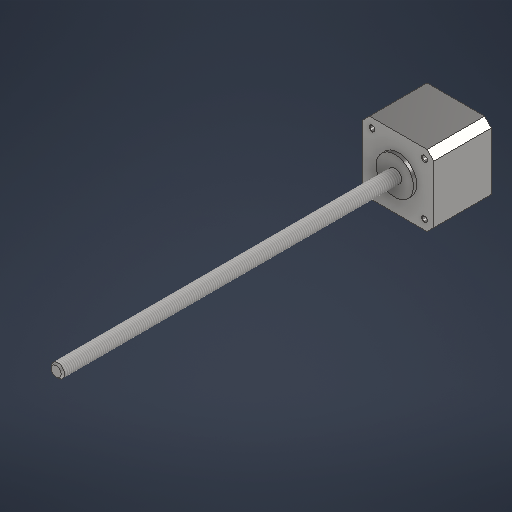
# Autodesk Inventor part: stepper_motor_42x34mm
Saved by Autodesk Inventor 2026.2 (Build 302298010, 298A)
## iProperties
Created: 2026-10-26
Part Number: stepper_motor_42x34mm
Material: Acier inoxydable
Document SubType Name: Modeling
Designer: User
Density: 8 g/cm^3
Appearance: Semi-poli
Author: User
Autodesk Inventor part; units mm, degrees
ref_plane "YZ Plane" through (0, 0, 0) normal (1, 0, 0) x (0, 1, 0)
ref_plane "XZ Plane" through (0, 0, 0) normal (0, 1, 0) x (-1, 0, 0)
ref_plane "XY Plane" through (0, 0, 0) normal (0, 0, 1) x (1, 0, 0)
sketch "Esquisse1" plane through (0, 0, 0) normal (0, 0, 1) x (1, 0, 0)
  line L0 (-21, 21) -> (21, 21)
  line L1 (21, 21) -> (21, -21)
  line L2 (21, -21) -> (-21, -21)
  line L3 (-21, -21) -> (-21, 21)
  point P0 (0, 0)
  dimension "d0" = 42
  dimension "d1" = 42
  dimension "d2" = 21
  dimension "d3" = 21
  constraints: 8 end point, 2 parallel, 1 horizontal, 1 perpendicular
  measures "d0" distance of L0.start L0.end
  measures "d1" distance of L2.end L0.start
  measures "d2" distance from line of L3 point (0, 0)
  measures "d3" distance from line of L2 point (0, 0)
extrude "Extrusion1" add sketch "Esquisse1" along normal blind 34
sketch "Esquisse2" plane through (0, 0, 34) normal (0, 0, 1) x (1, 0, 0)
  circle A0 centre (0, 0) radius 11
  dimension "d6" = 22
  constraints: 1 centre point, 1 coincident
  measures "d6" diameter of A0
extrude "Extrusion2" add sketch "Esquisse2" along normal blind 2
sketch "Esquisse3" plane through (0, 0, 36) normal (0, 0, 1) x (1, 0, 0)
  circle A0 centre (0, 0) radius 4
  circle A1 centre (0, 0) radius 11 projected
  dimension "d9" = 8
  constraints: 1 centre point, 1 concentric
  measures "d9" diameter of A0
extrude "Extrusion3" add sketch "Esquisse3" along normal blind 200 contours A0
chamfer "Chanfrein1" distance 4 angle 45 4 edges at (21, 21, 17) (21, -21, 17) (-21, -21, 17) (-21, 21, 17)
sketch "Esquisse5" plane through (0, 0, 34) normal (0, 0, 1) x (1, 0, 0)
  line L0 (17, 21) -> (-17, 21) projected
  line L1 (-21, 17) -> (-21, -17) projected
  circle A0 centre (-15.5, 15.5) radius 1.5
  point P0 (0, 0)
  dimension "d24" = 5.5
  dimension "d25" = 5.5
  dimension "d26" = 3
  constraints: 1 centre point
  measures "d24" distance from line of L0 A0.centre
  measures "d25" distance from line of L1 A0.centre
  measures "d26" diameter of A0
hole "Perçage2" at (-15.5, 15.5, 34) direction (0, 0, -1) diameter 3 depth 4.5 countersink diameter 3.5 countersink angle 90
pattern_circular "Réseau circulaire1" count 4 over 360 about axis through (0, 0, -10) along (0, 0, 1) of "Perçage2"
thread "Filetage1" size "M8x1.25" class "6g" standard "ANSI Metric M Profile" full length
chamfer "Chanfrein2" distance 1 angle 45 1 edges at (-4, 0, 236)
equation "\"d0\" = L_stepper_motor"
equation "\"d1\" = L_stepper_motor"
equation "\"d2\" = 0.5 * L_stepper_motor"
equation "\"d3\" = d2"
equation "\"d4\" = H_stepper_motor"
equation "\"d6\" = D_ledge"
equation "\"d7\" = H_ledge"
equation "\"d9\" = D_screw"
equation "\"d10\" = L_screw"
equation "\"L_stepper_motor\" = 42"
equation "\"H_stepper_motor\" = 34"
equation "\"L_screw\" = 200"
equation "\"D_screw\" = 8"
equation "\"H_ledge\" = 2"
equation "\"D_ledge\" = 22"
